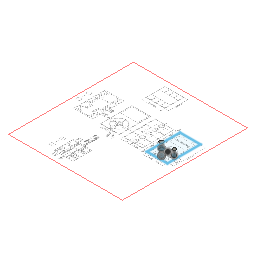
2022150mmGauge_WindVane_GeekServo360 (Autodesk Fusion 360 archive; units mm, degrees)
design "LegoServoBase"
Autodesk Fusion 360 part; units mm, degrees
note: some values were not read from the file. Set by a fixed rule: which face or edge a step refers to.
sketch "Sketch1" plane through (0, 0, 0) normal (0, 1, 0) x (1, 0, 0)
sketch "Sketch2" plane through (0, 0, 0) normal (0, 1, 0) x (1, 0, 0)
  circle A0 centre (55.8465, 2.6816) radius 2
  line L0 (55.8465, 2.6816) -> (39.8465, 2.6816)
  circle A1 centre (39.8465, 2.6816) radius 2.35
  circle A2 centre (47.8465, 2.6816) radius 2.35
  line L1 (39.8465, 2.6816) -> (51.1602, 2.6816) construction
  circle A3 centre (48.1647, -5.6366) radius 2.35
  line L2 (39.8465, 2.6816) -> (41.5082, 1.0199)
  line L3 (46.503, -3.9749) -> (48.1647, -5.6366)
  line L4 (35, 31) -> (60, 31)
  line L5 (60, 31) -> (60, -10)
  line L6 (60, -10) -> (35, -10)
  line L7 (35, -10) -> (35, 31)
  line L8 (34, 32) -> (61, 32)
  line L9 (61, 32) -> (61, -11)
  line L10 (61, -11) -> (34, -11)
  line L11 (34, -11) -> (34, 32)
  dimension "d1" = 4
  dimension "d2" = 16
  dimension "d3" = 4.7
  dimension "d8" = 4.7
  dimension "d14" = 45
  dimension "d15" = 4.7
  dimension "d23" = -1
  constraint coincident A0.centre L0.start
  constraint horizontal L0
  constraint coincident L0.end A1.centre
  constraint midpoint L0 A2.centre
  constraint horizontal L1
  constraint coincident A3.centre L3.end
  constraint coincident A1 L2.end
  constraint coincident A3 L3.start
  constraint collinear L2 L3
  constraint horizontal L4
  constraint vertical L5
  constraint horizontal L6
  constraint vertical L7
  measures "d1" diameter of A0
  measures "d2" distance of A0.centre L0.end
  measures "d3" diameter of A1
  measures "d8" diameter of A2
  measures "d14" angle of L1 L2
  measures "d15" diameter of A3
extrude "Extrude1" add sketch "Sketch2" along normal blind 5 contours L0 A1 L2 | L0 A1 L2 makes body 1
extrude "Extrude2" add sketch "Sketch2" along normal blind 5 separate body contours A0 makes body 2
extrude "Extrude4" add sketch "Sketch2" along normal blind 1 contours L0 A2 | L0 A2 bodies 1 2 makes body 3
move_face "OffsetFaces1" offset 10 2 faces at (50.1848, 0.3333, -2.4476) (45.5082, 0.3333, -2.9156) on bodies 3
extrude "Extrude5" add sketch "Sketch2" along normal blind 5 contours A3 bodies 3 2 1
move_face "OffsetFaces2" offset 1 1 faces at (54.6986, 5, -3.2344) on bodies 2
move_face "OffsetFaces3" offset 1 1 faces at (41.221, 5, -2.0756) on bodies 1
move_face "OffsetFaces4" offset 1 1 faces at (47.4589, 5, 5.5147) on bodies 3
move_face "OffsetFaces5" offset 1 1 faces at (50.7749, 0, -7.0727) on bodies 3
move_face "OffsetFaces6" offset 10 1 faces at (60.1811, -0.3333, -3.2972) on bodies 3
move_face "OffsetFaces7" offset 15 1 faces at (25.6076, -0.3333, -0.4563) on bodies 3
move_face "OffsetFaces8" offset -2 1 faces at (47.894, 1, -25.5204) on bodies 3
move_face "OffsetFaces9" offset -1 1 faces at (48.9132, -1, 6.0855) on bodies 3
move_face "OffsetFaces10" offset 1 1 faces at (39.5534, 6, -3.4161) on bodies 1
move_face "OffsetFaces11" offset 1 1 faces at (47.4589, 6, 5.2967) on bodies 3
move_face "OffsetFaces12" offset 1 1 faces at (56.9944, 6, -2.1288) on bodies 2
extrude "Extrude3" [suppressed]
